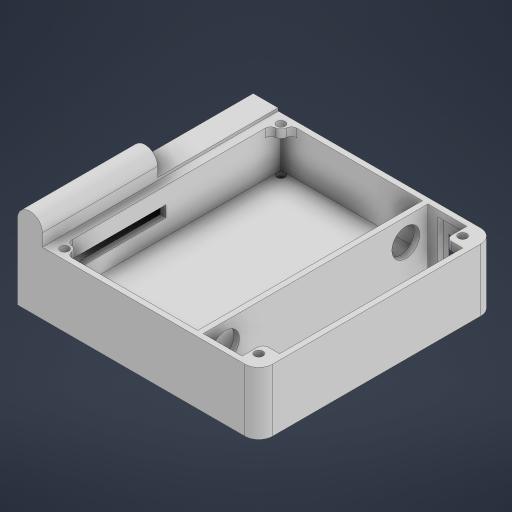
# Autodesk Inventor part: основа
Saved by Autodesk Inventor 2024 (Build 280153000, 153)
## iProperties
Created: 2026-05-29
Part Number: основа
Material: Типовые
Document SubType Name: Modeling
Designer: mitm
Density: 1 g/cm^3
Appearance: По умолчанию
Author: mitm
Autodesk Inventor part; units mm, degrees
ref_plane "YZ Plane" through (0, 0, 0) normal (1, 0, 0) x (0, 1, 0)
ref_plane "XZ Plane" through (0, 0, 0) normal (0, 1, 0) x (-1, 0, 0)
ref_plane "XY Plane" through (0, 0, 0) normal (0, 0, 1) x (1, 0, 0)
sketch "Эскиз1" plane through (0, 0, 0) normal (0, 1, 0) x (-1, 0, 0)
  line L0 (19.7795, 40.5) -> (-19.7795, 40.5)
  line L1 (-25.5, 34.7795) -> (-25.5, -34.7795)
  line L2 (-19.7795, -40.5) -> (19.7795, -40.5)
  line L3 (25.5, -34.7795) -> (25.5, 34.7795)
  line L4 (27.5, 42.5) -> (-27.5, 42.5)
  line L5 (-27.5, 42.5) -> (-27.5, -42.5)
  line L6 (-27.5, -42.5) -> (27.5, -42.5)
  line L7 (27.5, -42.5) -> (27.5, 42.5)
  line L8 (-27.5, 42.5) -> (-27.5, -42.5)
  line L9 (-27.5, -42.5) -> (-44.5, -42.5)
  line L10 (-49.5, -37.5) -> (-49.5, 37.5)
  line L11 (-44.5, 42.5) -> (-27.5, 42.5)
  line L12 (-27.5, 0) -> (-27.5, 33)
  line L13 (-27.5, 33) -> (-27.5, -33)
  line L14 (-47.5, -33) -> (-47.5, 33)
  line L15 (-27.5, 40.5) -> (-42.5, 40.5)
  line L16 (-47.5, 35.5) -> (-47.5, 33)
  line L17 (-27.5, -40.5) -> (-42.5, -40.5)
  line L18 (-47.5, -35.5) -> (-47.5, -33)
  circle A0 centre (-43.75, 36.75) radius 1.5
  circle A1 centre (-43.75, -36.75) radius 1.5
  circle A2 centre (24, 39) radius 1.5
  circle A3 centre (24, -39) radius 1.5
  arc A4 (21.7656, 38.7353) -> (23.7353, 36.7656) centre (24, 39) ccw
  arc A5 (23.7353, -36.7656) -> (21.7656, -38.7353) centre (24, -39) ccw
  arc A6 (-42.5, 40.5) -> (-47.5, 35.5) centre (-42.5, 35.5) ccw
  arc A7 (-44.5, 42.5) -> (-49.5, 37.5) centre (-44.5, 37.5) ccw
  arc A8 (-47.5, -35.5) -> (-42.5, -40.5) centre (-42.5, -35.5) ccw
  arc A9 (-49.5, -37.5) -> (-44.5, -42.5) centre (-44.5, -37.5) ccw
  arc A10 (19.7795, -40.5) -> (21.7656, -38.7353) centre (19.7795, -38.5) ccw
  arc A11 (23.7353, -36.7656) -> (25.5, -34.7795) centre (23.5, -34.7795) ccw
  arc A12 (21.7656, 38.7353) -> (19.7795, 40.5) centre (19.7795, 38.5) ccw
  arc A13 (25.5, 34.7795) -> (23.7353, 36.7656) centre (23.5, 34.7795) ccw
  line L19 (25.5, 40.5) -> (-25.5, 40.5)
  line L20 (-25.5, 40.5) -> (-25.5, -40.5)
  line L21 (-25.5, -40.5) -> (25.5, -40.5)
  line L22 (25.5, -40.5) -> (25.5, 40.5)
  line L23 (-27.5, 40.5) -> (-35, 40.5)
  line L24 (-27.5, 33) -> (-27.5, 40.5)
  line L25 (-47.5, 33) -> (-43.5, 33)
  line L26 (-37.5, 40.5) -> (-33.5, 40.5)
  line L27 (-37.5, 40.5) -> (-41.5, 40.5)
  line L28 (-41.5, 40.5) -> (-41.5, 35)
  arc A14 (-43.5, 33) -> (-41.5, 35) centre (-43.5, 35) ccw
  line L29 (-37.5, -40.5) -> (-33.5, -40.5)
  line L30 (-33.5, -40.5) -> (-41.5, -40.5)
  line L31 (-41.5, -40.5) -> (-41.5, -35)
  line L32 (-43.5, -33) -> (-47.5, -33)
  arc A15 (-41.5, -35) -> (-43.5, -33) centre (-43.5, -35) ccw
  line L33 (27.5, 42.5) -> (27.5, -42.5)
  line L34 (27.5, -42.5) -> (37.5, -42.5)
  line L35 (37.5, -42.5) -> (37.5, 42.5)
  line L36 (37.5, 42.5) -> (27.5, 42.5)
  line L37 (27.5, 40.5) -> (27.5, -40.5)
  line L38 (27.5, -40.5) -> (35.5, -40.5)
  line L39 (35.5, -40.5) -> (35.5, 40.5)
  line L40 (35.5, 40.5) -> (27.5, 40.5)
  point P0 (0, 0)
  point P1 (-49.5, -42.5)
  point P2 (-47.5, -40.5)
  point P3 (25.5, 37.3229)
  point P4 (22.3229, 40.5)
  point P5 (22.3229, -40.5)
  point P6 (25.5, -37.3229)
  point P7 (-41.5, -33)
  constraints: 82 end point, 28 point on circle, 23 point on line, 21 tangent, 16 centre point, 13 parallel, 12 perpendicular, 5 equal radius, 3 horizontal, 2 coincident, 1 collinear, 1 midpoint, 1 vertical, 3 other
extrude "Выдавливание1" add sketch "Эскиз1" along normal blind 16 contours L19 A2 L22 A13 A4 A12 | L19 L22 A2 | L22 A3 L21 A10 A5 A11 | L22 L21 A3 | L7 L6 L5 L4 | L36 L35 L34 L7 L38 L39 L40 | L5 L15 A6 L16 L14 L18 A8 L17 L9 A9 L10 A7 L11 | L28 A14 L25 L16 A6 L15 | L17 A8 L18 L32 A15 L31
extrude "Выдавливание2" cut sketch "Эскиз1" along normal blind 13 contours A12 A4 A13 L3 A11 A5 A10 L2 L21 L20 L1 L19 L0 | L19 A2 L22 A13 A4 A12 | L19 L22 A2 | A2 | L22 A3 L21 A10 A5 A11 | A3 | L22 L21 A3 | L5 L17 L31 A15 L32 L14 L25 A14 L28 L15 | L28 A14 L25 L16 A6 L15 | L17 A8 L18 L32 A15 L31
extrude "Выдавливание3" add sketch "Эскиз1" against normal blind 1.5 contours A12 A4 A13 L3 A11 A5 A10 L2 L21 L20 L1 L19 L0 | L19 A2 L22 A13 A4 A12 | L19 L22 A2 | L22 A3 L21 A10 A5 A11 | L22 L21 A3 | L7 L6 L5 L4 | L36 L35 L34 L7 L38 L39 L40 | L5 L15 A6 L16 L14 L18 A8 L17 L9 A9 L10 A7 L11 | L5 L17 L31 A15 L32 L14 L25 A14 L28 L15 | L28 A14 L25 L16 A6 L15 | L17 A8 L18 L32 A15 L31
extrude "Выдавливание4" add sketch "Эскиз1" against normal blind 6.5 contours L7 L6 L5 L4 | L36 L35 L34 L7 L38 L39 L40 | L5 L15 A6 L16 L14 L18 A8 L17 L9 A9 L10 A7 L11
extrude "Выдавливание5" add sketch "Эскиз1" along normal blind 16 contours L40 L39 L38 L7
extrude "Выдавливание6" cut sketch "Эскиз1" along normal blind 14 contours L40 L39 L38 L7
extrude "Выдавливание7" cut sketch "Эскиз1" against normal blind 14 contours L5 L17 L31 A15 L32 L14 L25 A14 L28 L15
sketch "Эскиз2" plane through (0, 14, 0) normal (0, -1, 0) x (1, 0, 0)
  line L0 (-27.5, -40.5) -> (-35.5, -40.5) projected
  line L1 (-35.5, -40.5) -> (-33.5, -40.5)
  line L2 (-33.5, -40.5) -> (-33.5, -20.5)
  line L3 (-33.5, -40.5) -> (-13.5, -40.5) construction
  line L4 (-33.5, -40.5) -> (-32.2, -40.5)
  line L5 (-32.2, -40.5) -> (-32.2, -20.5)
  line L6 (-32.2, -20.5) -> (-33.5, -20.5)
  line L7 (-35.5, -20.5) -> (-35.5, -40.5)
  line L8 (-32.2, -40.5) -> (-30.2, -40.5)
  line L9 (-30.2, -40.5) -> (-30.2, -20.5)
  line L10 (-30.2, -20.5) -> (-32.2, -20.5)
  line L11 (-33.5, -20.5) -> (-35.5, -20.5)
  point P0 (0, 0)
  dimension "d48" = 2
  dimension "d49" = 20
  dimension "d50" = 90
  dimension "d51" = 1.3
  dimension "d52" = 2
  constraints: 22 end point, 5 perpendicular, 5 point on line, 1 collinear, 1 horizontal, 1 vertical
  measures "d48" distance of L0.end L1.end
  measures "d49" distance of L1.end L2.end
  measures "d50" angle of L3 L2
  measures "d51" distance of L1.end L4.end
  measures "d52" distance of L4.end L8.end
extrude "Выдавливание8" add sketch "Эскиз2" along normal blind 3 contours L0 L5 L10 L9 | L0 L7 L11 L2
chamfer "Фаска1" distance 3 angle 45 2 edges at (-34.5, 11, -20.5) (-31.2, 11, -20.5)
sketch "Эскиз3" plane through (44.5, 16, -42.5) normal (0, 0, -1) x (-1, 0, 0)
  line L0 (74.7, -2) -> (74.7, -5) projected
  line L1 (74.7, -2) -> (74.7, -5)
  line L2 (76.7, -5) -> (76.7, -2) projected
  line L3 (74.7, -5) -> (76.7, -5)
  line L4 (76.7, -5) -> (76.7, -2)
  line L5 (78, -2) -> (78, -5) projected
  line L6 (76.7, -2) -> (78, -2)
  line L7 (78, -2) -> (78, -5)
  line L8 (78, -5) -> (80, -5) projected
  line L9 (78, -5) -> (80, -5)
  line L10 (80, -5) -> (80, -2)
  line L11 (78, -5) -> (78, -6)
  line L12 (78, -6) -> (76.7, -6)
  line L13 (76.7, -7.75) -> (76.7, -15)
  line L14 (74.95, -15) -> (73.2, -15)
  line L15 (73.2, -13.25) -> (73.2, -7.75)
  line L16 (73.2, -6) -> (74.95, -6)
  circle A0 centre (74.95, -7.75) radius 1.75
  circle A1 centre (74.95, -13.25) radius 1.75
  point P0 (44.5, -16)
  point P1 (76.7, -13.25)
  dimension "d58" = 1
  dimension "d59" = 9
  dimension "d60" = 3.5
  constraints: 26 end point, 7 perpendicular, 6 tangent, 5 point on circle, 3 collinear, 2 centre point, 2 point on line, 2 vertical
  measures "d58" distance of L5.end L11.end
  measures "d59" distance of L12.end L13.end
  measures "d60" distance of L13.end L14.end
extrude "Выдавливание9" cut sketch "Эскиз3" against normal blind 3
chamfer "Фаска2" distance 2 angle 45 4 edges at (-32.2, 5.5, -42.5) (-30.45, 1, -42.5) (-28.7, 5.5, -42.5) (-30.45, 10, -42.5)
sketch "Эскиз4" plane through (0, 16, 0) normal (0, 1, 0) x (1, 0, 0)
  line L0 (-27.5, -40.5) -> (-27.5, 40.5) projected
  line L1 (-27.5, -40.5) -> (-27.5, 0)
  line L2 (-27.5, 0) -> (-35.5, 0)
  line L3 (-35.5, 0) -> (-35.5, -40.5)
  line L4 (-35.5, -40.5) -> (-27.5, -40.5)
  line L5 (-34.5, -39.5) -> (-34.5, -1)
  line L6 (-34.5, -1) -> (-28.5, -1)
  line L7 (-28.5, -1) -> (-28.5, -39.5)
  line L8 (-28.5, -39.5) -> (-34.5, -39.5)
  point P0 (0, 0)
  dimension "d66" = 1
  constraints: 16 end point, 4 parallel, 2 perpendicular, 1 midpoint, 3 other
  measures "d66" distance between parallel lines of L3 L5
extrude "Выдавливание10" cut sketch "Эскиз4" against normal blind 3 contours L5 L6 L7 L8
sketch "Эскиз5" plane through (-25.5, 16, 34.7795) normal (1, 0, 0) x (0, 0, -1)
  line L0 (-5.7205, -16) -> (34.7795, -16)
  line L1 (34.7795, -16) -> (34.7795, 0)
  line L2 (34.7795, 0) -> (-5.7205, 0)
  line L3 (-5.7205, 0) -> (-5.7205, -16)
  line L4 (-4.7205, -1) -> (33.7795, -1)
  line L5 (33.7795, -1) -> (33.7795, -15)
  line L6 (33.7795, -15) -> (-4.7205, -15)
  line L7 (-4.7205, -15) -> (-4.7205, -1)
  line L8 (33.7795, -1) -> (33.7795, -8)
  line L9 (33.7795, -8) -> (-4.7205, -8)
  line L10 (33.7795, -8) -> (33.7795, -6)
  line L11 (33.7795, -6) -> (-4.7205, -6)
  line L12 (33.7795, -8) -> (33.7795, -10)
  line L13 (33.7795, -10) -> (-4.7205, -10)
  line L14 (-4.7205, -6) -> (-4.7205, -10)
  dimension "d69" = 1
  dimension "d70" = 7
  dimension "d71" = 2
  dimension "d72" = 2
  constraints: 30 end point, 5 perpendicular, 4 parallel, 4 point on line, 2 midpoint, 1 horizontal, 3 other
  measures "d69" distance between parallel lines of L2 L4
  measures "d70" distance of L4.end L8.end
  measures "d71" distance of L8.end L10.end
  measures "d72" distance of L8.end L12.end
extrude "Выдавливание11" cut sketch "Эскиз5" against normal blind 3 contours L11 L5 L9 L7 | L9 L5 L13 L7
sketch "Эскиз6" plane through (25.5, 16, -40.5) normal (-1, 0, 0) x (0, 0, 1)
  line L0 (0, -16) -> (81, -16) projected
  line L1 (0, -16) -> (81, -16)
  line L2 (81, -16) -> (81, 0)
  line L3 (81, 0) -> (0, 0)
  line L4 (0, 0) -> (0, -16)
  circle A0 centre (8, -8) radius 8
  circle A1 centre (8, -8) radius 5
  circle A2 centre (73, -8) radius 8
  circle A3 centre (73, -8) radius 5
  point P0 (40.5, -16)
  dimension "d75" = 3
  dimension "d76" = 3
  constraints: 8 end point, 6 tangent, 4 centre point, 3 equal length, 1 perpendicular
  measures "d75" radial gap between concentric circles of A0 A1
  measures "d76" radial gap between concentric circles of A2 A3
extrude "Выдавливание12" cut sketch "Эскиз6" against normal blind 3 contours A1 | A3
sketch "Эскиз7" plane through (44.5, 16, -42.5) normal (0, 0, -1) x (-1, 0, 0)
  line L0 (0, 0) -> (82, 0) projected
  line L1 (0, 0) -> (0, -22.5) projected
  line L2 (0, 0) -> (0, -22.5)
  line L3 (0, -22.5) -> (17, -22.5)
  line L4 (17, -22.5) -> (17, 0)
  line L5 (17, 0) -> (0, 0)
  line L6 (0, -22.5) -> (17, 0)
  line L7 (0, 0) -> (17, -22.5)
  line L8 (4.5, -19) -> (12.5, -19)
  line L9 (12.5, -19) -> (12.5, -3.5)
  line L10 (12.5, -3.5) -> (4.5, -3.5)
  line L11 (4.5, -3.5) -> (4.5, -19)
  line L12 (4.5, -19) -> (12.5, -3.5) construction
  line L13 (12.5, -19) -> (4.5, -3.5) construction
  line L14 (6.5, -15.75) -> (10.5, -15.75)
  line L15 (10.5, -15.75) -> (10.5, -6.75)
  line L16 (10.5, -6.75) -> (6.5, -6.75)
  line L17 (6.5, -6.75) -> (6.5, -15.75)
  line L18 (6.5, -15.75) -> (10.5, -6.75) construction
  line L19 (10.5, -15.75) -> (6.5, -6.75) construction
  point P0 (44.5, -16)
  point P1 (8.5, -11.25)
  point P2 (8.5, -11.25)
  dimension "d79" = 8
  dimension "d80" = 15.5
  dimension "d81" = 4
  dimension "d82" = 9
  constraints: 36 end point, 7 equal length, 6 midpoint, 3 perpendicular, 2 horizontal
  measures "d79" distance of L10.end L9.end
  measures "d80" distance of L9.end L8.end
  measures "d81" distance of L16.end L15.end
  measures "d82" distance of L15.end L14.end
extrude "Выдавливание13" cut sketch "Эскиз7" against normal blind 3 contours L17 L16 L15 L6 L7 | L7 L6 L17 | L15 L7 L6 | L6 L7 L15 L14 L17
sketch "Эскиз8" plane through (27.5, 16, -40.5) normal (0, 0, 1) x (1, 0, 0)
  line L0 (6.5, -6.75) -> (10.5, -6.75) projected
  line L1 (10.5, -6.75) -> (6.5, -6.75)
  line L2 (10.5, -15.75) -> (6.5, -15.75) projected
  line L3 (6.5, -6.75) -> (6.5, -15.75)
  line L4 (6.5, -15.75) -> (10.5, -15.75)
  line L5 (10.5, -15.75) -> (10.5, -6.75)
  line L6 (10.5, -6.75) -> (6.5, -15.75)
  line L7 (10.5, -15.75) -> (6.5, -6.75)
  line L8 (12.5, -3.25) -> (4.5, -3.25)
  line L9 (4.5, -3.25) -> (4.5, -19.25)
  line L10 (4.5, -19.25) -> (12.5, -19.25)
  line L11 (12.5, -19.25) -> (12.5, -3.25)
  line L12 (12.5, -3.25) -> (4.5, -19.25) construction
  line L13 (4.5, -3.25) -> (12.5, -19.25) construction
  point P0 (-27.5, -16)
  point P1 (8.5, -11.25)
  dimension "d85" = 8
  dimension "d86" = 16
  constraints: 24 end point, 4 perpendicular, 3 midpoint, 2 horizontal, 2 parallel
  measures "d85" distance of L10.end L9.end
  measures "d86" distance of L9.end L8.end
extrude "Выдавливание14" cut sketch "Эскиз8" against normal blind 1
chamfer "Фаска3" distance 1 angle 45 4 edges at (38, 4.75, -42.5) (36, 0.25, -42.5) (34, 4.75, -42.5) (36, 9.25, -42.5)
chamfer "Фаска4" distance 1 angle 45 4 edges at (40, 4.75, -40.5) (36, -3.25, -40.5) (32, 4.75, -40.5) (36, 12.75, -40.5)
sketch "Эскиз9" plane through (-37.5, 16, 42.5) normal (0, 0, 1) x (1, 0, 0)
  line L0 (12, 0) -> (12, -3) projected
  line L1 (0, 0) -> (82, 0) projected
  line L2 (12, 0) -> (0, 0)
  line L3 (3, 0) -> (9, 0) projected
  line L4 (9, 0) -> (0, 0)
  line L5 (0, 0) -> (0, 5)
  line L6 (0, -22.5) -> (0, 0) projected
  line L7 (0, 0) -> (3, 0)
  line L8 (0, 0) -> (9, 0)
  line L9 (9, 0) -> (9, 9)
  line L10 (9, 9) -> (0, 9)
  line L11 (0, 9) -> (0, 0)
  circle A0 centre (4.5, 4.5) radius 4.5
  circle A1 centre (4.5, 4.5) radius 3.5
  circle A2 centre (4.5, 4.5) radius 2.5
  point P0 (37.5, -16)
  point P1 (0, 4.5)
  point P2 (9, 4.5)
  dimension "d95" = 5
  dimension "d96" = 3
  dimension "d97" = 9
  dimension "d98" = 7
  dimension "d99" = 5
  constraints: 16 end point, 4 collinear, 3 centre point, 3 tangent, 2 coincident, 2 parallel, 2 perpendicular, 1 point on line
  measures "d95" distance of L1.start L5.end
  measures "d96" distance of L1.start L3.start
  measures "d97" distance of L9.end L3.end
  measures "d98" diameter of A1
  measures "d99" diameter of A2
extrude "Выдавливание15" add sketch "Эскиз9" against normal blind 3 contours L5 A0 L1 | A0 | A0 L9 L1 | A1 | A2
extrude "Выдавливание16" add sketch "Эскиз9" against normal blind 41.5 contours L5 A0 L1 | A0 | A0 L9 L1
sketch "Эскиз10" plane through (0, 16, 0) normal (0, 1, 0) x (1, 0, 0)
  line L0 (-34.5, -1) -> (-34.5, -39.5) projected
  line L1 (-36.5, -1) -> (-29.5, -1) projected
  line L2 (-34.5, -1) -> (-31.5, -1)
  line L3 (-31.5, -1) -> (-31.5, -39.5)
  line L4 (-31.5, -39.5) -> (-34.5, -39.5)
  line L5 (-34.5, -39.5) -> (-34.5, -1)
  point P0 (0, 0)
  dimension "d104" = 3
  constraints: 8 end point, 2 parallel, 1 perpendicular, 1 point on line
  measures "d104" distance of L0.start L2.end
extrude "Выдавливание17" cut sketch "Эскиз10" along normal blind 2
sketch "Эскиз11" plane through (-28.5, 16, 1) normal (0, -1, 0) x (1, 0, 0)
  line L0 (0, 0) -> (-6, 0) projected
  line L1 (-6, 38.5) -> (0, 38.5) projected
  line L2 (-3, 0) -> (-3, 38.5)
  line L3 (-3, 38.5) -> (0, 38.5)
  line L4 (0, 38.5) -> (0, 0)
  line L5 (0, 0) -> (-3, 0)
  point P0 (28.5, -1)
  constraints: 8 end point, 2 midpoint, 2 parallel, 1 perpendicular
extrude "Выдавливание18" add sketch "Эскиз11" along normal blind 2
sketch "Эскиз12" plane through (0, 16, 0) normal (0, 1, 0) x (1, 0, 0)
  line L0 (-28.5, -1) -> (-37.5, -1) projected
  line L1 (-37.5, 42.5) -> (-37.5, -1) projected
  line L2 (-37.5, -1) -> (-37.5, 42.5)
  line L3 (-37.5, 42.5) -> (-28.5, 42.5)
  line L4 (-28.5, 42.5) -> (-28.5, -1)
  line L5 (-28.5, -1) -> (-37.5, -1)
  point P0 (0, 0)
  dimension "d109" = 9
  constraints: 8 end point, 3 equal length, 1 perpendicular
  measures "d109" distance of L1.start L3.end
extrude "Выдавливание19" add sketch "Эскиз12" along normal blind 1
